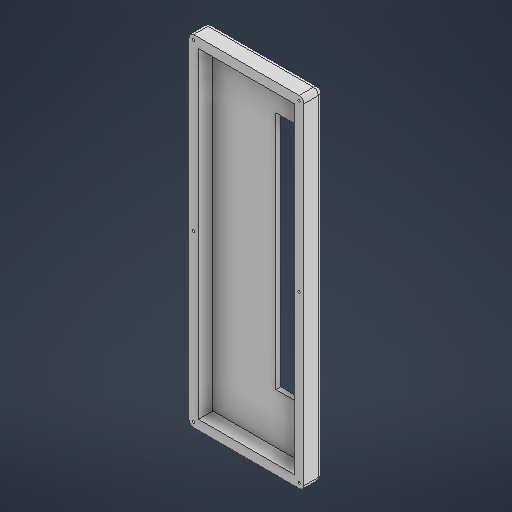
# Autodesk Inventor part: Parte delantera
Saved by Autodesk Inventor 2026 (Build 300175050, 175E)
## iProperties
Created: 2026-02-11
Part Number: Parte delantera
Material: Genérico
Document SubType Name: Modeling
Designer: Pablo
Density: 1 g/cm^3
Appearance: Valor por defecto
Author: Pablo
Autodesk Inventor part; units mm, degrees
ref_plane "YZ Plane" through (0, 0, 0) normal (1, 0, 0) x (0, 1, 0)
ref_plane "XZ Plane" through (0, 0, 0) normal (0, 1, 0) x (-1, 0, 0)
ref_plane "XY Plane" through (0, 0, 0) normal (0, 0, 1) x (1, 0, 0)
sketch "Boceto1" plane through (0, 0, 0) normal (0, 0, 1) x (1, 0, 0)
  line L0 (0, 279.8883) -> (0, -279.8883)
  line L1 (-153.0726, 0) -> (153.0726, 0)
  line L2 (-100, 335) -> (100, 335)
  line L3 (100, 335) -> (100, -335)
  line L4 (100, -335) -> (-100, -335)
  line L5 (-100, -335) -> (-100, 335)
  line L6 (-120, 355) -> (120, 355)
  line L7 (120, 355) -> (120, -355)
  line L8 (120, -355) -> (-120, -355)
  line L9 (-120, -355) -> (-120, 355)
  line L10 (40, 355) -> (40, 335)
  line L11 (70, 355) -> (70, 335)
  line L12 (-110, 345) -> (-110, -345)
  line L13 (-110, -345) -> (110, -345)
  line L14 (110, -345) -> (110, 345)
  line L15 (110, 345) -> (-110, 345)
  circle A0 centre (-110, 345) radius 2.5
  circle A1 centre (110, 345) radius 2.5
  circle A2 centre (110, 0) radius 2.5
  circle A3 centre (110, -345) radius 2.5
  circle A4 centre (-110, -345) radius 2.5
  circle A5 centre (-110, 0) radius 2.5
  line L16 (-100, 309.5) -> (37, 309.5)
  line L17 (37, 309.5) -> (37, -309.5)
  line L18 (37, -309.5) -> (-100, -309.5)
  line L19 (-100, -309.5) -> (-100, 309.5)
  line L20 (-31.5, 316.3518) -> (-31.5, -305.1898)
  line L21 (-105, 316.3518) -> (42, 316.3518)
  line L22 (42, 316.3518) -> (42, -316.3518)
  line L23 (42, -316.3518) -> (-105, -316.3518)
  line L24 (-105, -316.3518) -> (-105, 316.3518)
  line L25 (37, 282.283) -> (42, 282.283)
  line L26 (37, 257.283) -> (42, 257.283)
  line L27 (-86.5, 269.5) -> (-31.5, 269.5)
  line L28 (-31.5, 269.5) -> (-31.5, -230.5)
  line L29 (-31.5, -230.5) -> (-86.5, -230.5)
  line L30 (-86.5, -230.5) -> (-86.5, 269.5)
  line L31 (86.5, 269.5) -> (31.5, 269.5)
  line L32 (31.5, 269.5) -> (31.5, -230.5)
  line L33 (31.5, -230.5) -> (86.5, -230.5)
  line L34 (86.5, -230.5) -> (86.5, 269.5)
  point P0 (0, 0)
  point P1 (0, 0)
  point P2 (0, 335)
  point P3 (100, 0)
  point P4 (0, 355)
  point P5 (120, 0)
  point P6 (37, 0)
  point P7 (-31.5, 309.5)
  point P8 (42, 0)
  dimension "d0" = 200
  dimension "d1" = 670
  dimension "d2" = 20
  dimension "d3" = 20
  dimension "d4" = 30
  dimension "d5" = 40
  dimension "d7" = 5
  dimension "d8" = 5
  dimension "d9" = 5
  dimension "d10" = 5
  dimension "d11" = 5
  dimension "d12" = 5
  dimension "d22" = 5
  dimension "d23" = 619
  dimension "d24" = 137
  dimension "d25" = 0
  dimension "d27" = 25
  dimension "d28" = 55
  dimension "d29" = 500
  dimension "d30" = 40
  constraints: 71 end point, 17 point on line, 12 midpoint, 10 horizontal, 10 parallel, 6 centre point, 6 vertical, 5 coincident, 5 perpendicular, 4 symmetric about line, 4 other
  measures "d0" distance between parallel lines of L3 L5
  measures "d1" distance between parallel lines of L4 L2
  measures "d2" distance between parallel lines of L2 L6
  measures "d3" distance between parallel lines of L7 L3
  measures "d4" distance between parallel lines of L10 L11
  measures "d5" distance between parallel lines of L10 L0
  measures "d7" diameter of A0
  measures "d8" diameter of A1
  measures "d9" diameter of A2
  measures "d10" diameter of A3
  measures "d11" diameter of A4
  measures "d12" diameter of A5
  measures "d22" distance between parallel lines of L17 L22
  measures "d23" distance between parallel lines of L18 L16
  measures "d24" distance between parallel lines of L17 L19
  measures "d25" distance between parallel lines of L5 L19
  measures "d27" distance between parallel lines of L26 L25
  measures "d28" distance between parallel lines of L30 L20
  measures "d29" distance between parallel lines of L29 L27
  measures "d30" distance between parallel lines of L16 L27
extrude "Extrusión1" add sketch "Boceto1" along normal blind 40 contours L9 L6 L10 L15 A0 L12 A5 L1 | L1 A5 L12 A4 L13 A3 L14 A2 L7 L8 L9 | A5 L12 L1 | L1 L12 A5 | L12 A5 L1 | L1 A5 L12 | L12 A0 L15 L10 L2 L5 L21 L24 L1 A5 | A5 L1 L24 L23 L5 L4 L3 A2 L14 A3 L13 A4 L12 | L6 L11 L15 L10 | A0 L15 L12 | L12 L15 A0 | A4 L13 L12 | L12 L13 A4 | L1 A2 L14 A1 L15 L11 L6 L7 | L15 L11 L2 L10 | L24 L21 L5 L1 | L1 L5 L23 L24 | A2 L14 L1 | L1 L14 A2 | L15 A1 L14 A2 L1 L3 L2 L11 | A3 L14 L13 | L13 L14 A3 | L14 A2 L1 | L1 A2 L14 | A1 L14 L15 | L15 L14 A1
extrude "Extrusión2" add sketch "Boceto1" along normal blind 10 contours L2 L3 L1 L34 L31 L22 L21 L5 | L5 L16 L20 L27 L30 L1 | L1 L30 L29 L20 L32 L33 L17 L18 L5 | L30 L27 L20 L1 | L1 L20 L29 L30 | L18 L17 L33 L22 L23 L5 | L5 L21 L20 L16 | L23 L22 L33 L34 L1 L3 L4 L5 | L20 L16 L17 L31 L32 L1 | L20 L21 L22 L25 L17 L16 | L33 L32 L1 L17 | L17 L1 L22 L33 | L22 L1 L34 L33 | L1 L22 L31 L34 | L32 L31 L17 L1 | L17 L26 L22 L1 | L25 L22 L31 L17 | L17 L31 L22 L26
fillet "Empalme1" radius 10 8 edges at (120, 355, 20) (-120, 355, 20) (120, -355, 20) (-120, -355, 20) (0, 355, 0) (-120, 0, 0) (120, 0, 0) (0, -355, 0)
extrude "Extrusión4" cut sketch "Boceto1" along normal up to surface (30 mm away) from surface at 10 contours A5 L12 L1 | L1 L12 A5 | L12 A5 L1 | L1 A5 L12 | A0 L15 L12 | L12 L15 A0 | A4 L13 L12 | L12 L13 A4 | A2 L14 L1 | L1 L14 A2 | A3 L14 L13 | L13 L14 A3 | L14 A2 L1 | L1 A2 L14 | A1 L14 L15 | L15 L14 A1
extrude "Extrusión6" cut sketch "Boceto1" along normal blind 10 contours L33 L32 L1 L17 | L17 L1 L22 L33 | L22 L1 L34 L33 | L1 L22 L31 L34 | L32 L31 L17 L1 | L17 L26 L22 L1 | L17 L31 L22 L26
